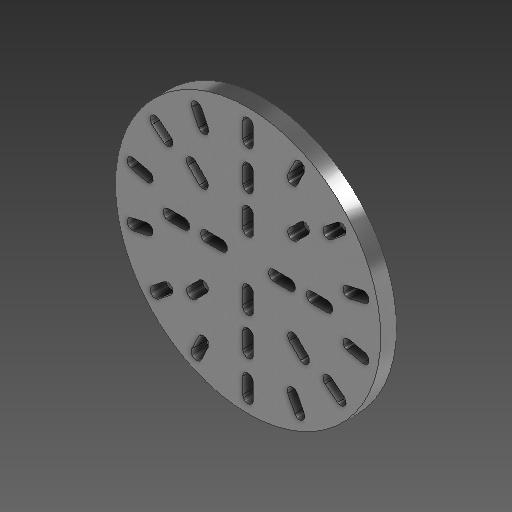
# Autodesk Inventor part: Circule pattern
Saved by Autodesk Inventor 2026.1 (Build 301233020, 233B)
## iProperties
Created: 2026-08-12
Part Number: Circule pattern
Material: Generic
Document SubType Name: Modeling
Designer: YmCris
Density: 1 g/cm^3
Appearance: Default
Author: YmCris
Autodesk Inventor part; units mm, degrees
ref_plane "YZ Plane" through (0, 0, 0) normal (1, 0, 0) x (0, 1, 0)
ref_plane "XZ Plane" through (0, 0, 0) normal (0, 1, 0) x (-1, 0, 0)
ref_plane "XY Plane" through (0, 0, 0) normal (0, 0, 1) x (1, 0, 0)
sketch "Sketch1" plane through (0, 0, 0) normal (0, 0, 1) x (1, 0, 0)
  circle A0 centre (0, 0) radius 1270
  line L0 (0, 0) -> (0, 1270)
  line L1 (0, 1270) -> (0, 635)
  line L2 (0, 1270) -> (0, 952.5)
  line L3 (50.8, 1136.3047) -> (50.8, 983.9047)
  line L4 (-50.8, 983.9047) -> (-50.8, 1136.3047)
  arc A1 (50.6913, 1136.3047) -> (-50.6913, 1136.3047) centre (0, 1136.3047) ccw
  line L5 (-50.8, 1136.3047) -> (-50.6913, 1136.3047)
  line L6 (50.6913, 1136.3047) -> (50.8, 1136.3047)
  arc A2 (-50.6913, 983.9047) -> (50.6913, 983.9047) centre (0, 983.9047) ccw
  line L7 (50.8, 983.9047) -> (50.6913, 983.9047)
  line L8 (-50.6913, 983.9047) -> (-50.8, 983.9047)
  line L9 (50.8, 609.0872) -> (50.8, 761.4872)
  line L10 (-50.8, 761.4872) -> (-50.8, 609.0872)
  arc A3 (50.6426, 761.4872) -> (-50.6426, 761.4872) centre (0, 761.4872) ccw
  line L11 (50.8, 761.4872) -> (50.6426, 761.4872)
  line L12 (-50.6426, 761.4872) -> (-50.8, 761.4872)
  arc A4 (-50.6426, 609.0872) -> (50.6426, 609.0872) centre (0, 609.0872) ccw
  line L13 (-50.8, 609.0872) -> (-50.6426, 609.0872)
  line L14 (50.6426, 609.0872) -> (50.8, 609.0872)
  line L15 (50.8, 401.6242) -> (50.8, 249.2242)
  line L16 (-50.8, 249.2242) -> (-50.8, 401.6242)
  arc A5 (50.8, 390.8967) -> (-50.8, 390.8967) centre (0, 401.6242) ccw
  line L17 (0, 325.4242) -> (22.9942, 325.4242)
  arc A6 (-50.8, 259.9518) -> (50.8, 259.9518) centre (0, 249.2242) ccw
  arc A7 (-472.5715, 864.4733) -> (-381.229, 908.4616) centre (-426.9002, 886.4675) ccw
  line L18 (-381.131, 908.5088) -> (-381.229, 908.4616)
  line L19 (-472.5715, 864.4733) -> (-472.6694, 864.4262)
  line L20 (-447.2549, 1045.8164) -> (-381.131, 908.5088)
  line L21 (-472.6694, 864.4262) -> (-538.7933, 1001.7338)
  line L22 (-447.3528, 1045.7692) -> (-447.2549, 1045.8164)
  arc A8 (-447.3528, 1045.7692) -> (-538.6954, 1001.781) centre (-493.0241, 1023.7751) ccw
  line L23 (-538.7933, 1001.7338) -> (-538.6954, 1001.781)
  arc A9 (-800.8531, 573.8225) -> (-737.6421, 653.0866) centre (-769.2476, 613.4545) ccw
  line L24 (-737.5744, 653.1716) -> (-737.6421, 653.0866)
  line L25 (-800.8531, 573.8225) -> (-800.9209, 573.7375)
  line L26 (-856.7255, 748.1914) -> (-737.5744, 653.1716)
  line L27 (-800.9209, 573.7375) -> (-920.072, 668.7573)
  line L28 (-856.7933, 748.1064) -> (-856.7255, 748.1914)
  arc A10 (-856.7933, 748.1064) -> (-920.0043, 668.8423) centre (-888.3988, 708.4744) ccw
  line L29 (-920.072, 668.7573) -> (-920.0043, 668.8423)
  arc A11 (-970.516, 169.519) -> (-947.9562, 268.3597) centre (-959.2361, 218.9394) ccw
  line L30 (-947.932, 268.4657) -> (-947.9562, 268.3597)
  line L31 (-970.516, 169.519) -> (-970.5402, 169.413)
  line L32 (-1096.5111, 302.3779) -> (-947.932, 268.4657)
  line L33 (-970.5402, 169.413) -> (-1119.1192, 203.3252)
  line L34 (-1096.5353, 302.2719) -> (-1096.5111, 302.3779)
  arc A12 (-1096.5353, 302.2719) -> (-1119.095, 203.4312) centre (-1107.8151, 252.8516) ccw
  line L35 (-1119.1192, 203.3252) -> (-1119.095, 203.4312)
  arc A13 (-947.9562, -268.3597) -> (-970.516, -169.519) centre (-959.2361, -218.9394) ccw
  line L36 (-970.5402, -169.413) -> (-970.516, -169.519)
  line L37 (-947.9562, -268.3597) -> (-947.932, -268.4657)
  line L38 (-1119.1192, -203.3252) -> (-970.5402, -169.413)
  line L39 (-947.932, -268.4657) -> (-1096.5111, -302.3779)
  line L40 (-1119.095, -203.4312) -> (-1119.1192, -203.3252)
  arc A14 (-1119.095, -203.4312) -> (-1096.5353, -302.2719) centre (-1107.8151, -252.8516) ccw
  line L41 (-1096.5111, -302.3779) -> (-1096.5353, -302.2719)
  arc A15 (-737.6421, -653.0866) -> (-800.8531, -573.8225) centre (-769.2476, -613.4545) ccw
  line L42 (-800.9209, -573.7375) -> (-800.8531, -573.8225)
  line L43 (-737.6421, -653.0866) -> (-737.5744, -653.1716)
  line L44 (-920.072, -668.7573) -> (-800.9209, -573.7375)
  line L45 (-737.5744, -653.1716) -> (-856.7255, -748.1914)
  line L46 (-920.0043, -668.8423) -> (-920.072, -668.7573)
  arc A16 (-920.0043, -668.8423) -> (-856.7933, -748.1064) centre (-888.3988, -708.4744) ccw
  line L47 (-856.7255, -748.1914) -> (-856.7933, -748.1064)
  arc A17 (-381.229, -908.4616) -> (-472.5715, -864.4733) centre (-426.9002, -886.4675) ccw
  line L48 (-472.6694, -864.4262) -> (-472.5715, -864.4733)
  line L49 (-381.229, -908.4616) -> (-381.131, -908.5088)
  line L50 (-538.7933, -1001.7338) -> (-472.6694, -864.4262)
  line L51 (-381.131, -908.5088) -> (-447.2549, -1045.8164)
  line L52 (-538.6954, -1001.781) -> (-538.7933, -1001.7338)
  arc A18 (-538.6954, -1001.781) -> (-447.3528, -1045.7692) centre (-493.0241, -1023.7751) ccw
  line L53 (-447.2549, -1045.8164) -> (-447.3528, -1045.7692)
  arc A19 (50.6913, -983.9047) -> (-50.6913, -983.9047) centre (0, -983.9047) ccw
  line L54 (-50.8, -983.9047) -> (-50.6913, -983.9047)
  line L55 (50.6913, -983.9047) -> (50.8, -983.9047)
  line L56 (-50.8, -1136.3047) -> (-50.8, -983.9047)
  line L57 (50.8, -983.9047) -> (50.8, -1136.3047)
  line L58 (-50.6913, -1136.3047) -> (-50.8, -1136.3047)
  arc A20 (-50.6913, -1136.3047) -> (50.6913, -1136.3047) centre (0, -1136.3047) ccw
  line L59 (50.8, -1136.3047) -> (50.6913, -1136.3047)
  arc A21 (472.5715, -864.4733) -> (381.229, -908.4616) centre (426.9002, -886.4675) ccw
  line L60 (381.131, -908.5088) -> (381.229, -908.4616)
  line L61 (472.5715, -864.4733) -> (472.6694, -864.4262)
  line L62 (447.2549, -1045.8164) -> (381.131, -908.5088)
  line L63 (472.6694, -864.4262) -> (538.7933, -1001.7338)
  line L64 (447.3528, -1045.7692) -> (447.2549, -1045.8164)
  arc A22 (447.3528, -1045.7692) -> (538.6954, -1001.781) centre (493.0241, -1023.7751) ccw
  line L65 (538.7933, -1001.7338) -> (538.6954, -1001.781)
  arc A23 (800.8531, -573.8225) -> (737.6421, -653.0866) centre (769.2476, -613.4545) ccw
  line L66 (737.5744, -653.1716) -> (737.6421, -653.0866)
  line L67 (800.8531, -573.8225) -> (800.9209, -573.7375)
  line L68 (856.7255, -748.1914) -> (737.5744, -653.1716)
  line L69 (800.9209, -573.7375) -> (920.072, -668.7573)
  line L70 (856.7933, -748.1064) -> (856.7255, -748.1914)
  arc A24 (856.7933, -748.1064) -> (920.0043, -668.8423) centre (888.3988, -708.4744) ccw
  line L71 (920.072, -668.7573) -> (920.0043, -668.8423)
  arc A25 (970.516, -169.519) -> (947.9562, -268.3597) centre (959.2361, -218.9394) ccw
  line L72 (947.932, -268.4657) -> (947.9562, -268.3597)
  line L73 (970.516, -169.519) -> (970.5402, -169.413)
  line L74 (1096.5111, -302.3779) -> (947.932, -268.4657)
  line L75 (970.5402, -169.413) -> (1119.1192, -203.3252)
  line L76 (1096.5353, -302.2719) -> (1096.5111, -302.3779)
  arc A26 (1096.5353, -302.2719) -> (1119.095, -203.4312) centre (1107.8151, -252.8516) ccw
  line L77 (1119.1192, -203.3252) -> (1119.095, -203.4312)
  arc A27 (947.9562, 268.3597) -> (970.516, 169.519) centre (959.2361, 218.9394) ccw
  line L78 (970.5402, 169.413) -> (970.516, 169.519)
  line L79 (947.9562, 268.3597) -> (947.932, 268.4657)
  line L80 (1119.1192, 203.3252) -> (970.5402, 169.413)
  line L81 (947.932, 268.4657) -> (1096.5111, 302.3779)
  line L82 (1119.095, 203.4312) -> (1119.1192, 203.3252)
  arc A28 (1119.095, 203.4312) -> (1096.5353, 302.2719) centre (1107.8151, 252.8516) ccw
  line L83 (1096.5111, 302.3779) -> (1096.5353, 302.2719)
  arc A29 (737.6421, 653.0866) -> (800.8531, 573.8225) centre (769.2476, 613.4545) ccw
  line L84 (800.9209, 573.7375) -> (800.8531, 573.8225)
  line L85 (737.6421, 653.0866) -> (737.5744, 653.1716)
  line L86 (920.072, 668.7573) -> (800.9209, 573.7375)
  line L87 (737.5744, 653.1716) -> (856.7255, 748.1914)
  line L88 (920.0043, 668.8423) -> (920.072, 668.7573)
  arc A30 (920.0043, 668.8423) -> (856.7933, 748.1064) centre (888.3988, 708.4744) ccw
  line L89 (856.7255, 748.1914) -> (856.7933, 748.1064)
  arc A31 (381.229, 908.4616) -> (472.5715, 864.4733) centre (426.9002, 886.4675) ccw
  line L90 (472.6694, 864.4262) -> (472.5715, 864.4733)
  line L91 (381.229, 908.4616) -> (381.131, 908.5088)
  line L92 (538.7933, 1001.7338) -> (472.6694, 864.4262)
  line L93 (381.131, 908.5088) -> (447.2549, 1045.8164)
  line L94 (538.6954, 1001.781) -> (538.7933, 1001.7338)
  arc A32 (538.6954, 1001.781) -> (447.3528, 1045.7692) centre (493.0241, 1023.7751) ccw
  line L95 (447.2549, 1045.8164) -> (447.3528, 1045.7692)
  line L96 (0, 0) -> (-898.0256, 898.0256)
  line L97 (-898.0256, 898.0256) -> (-449.0128, 449.0128)
  arc A33 (-502.643, 574.2625) -> (-574.2625, 502.643) centre (-538.4527, 538.4527) ccw
  line L98 (-502.5317, 574.3738) -> (-502.643, 574.2625)
  line L99 (-574.2625, 502.643) -> (-574.3738, 502.5317)
  line L100 (-394.7686, 466.6107) -> (-502.5317, 574.3738)
  line L101 (-574.3738, 502.5317) -> (-466.6107, 394.7686)
  line L102 (-394.8799, 466.4994) -> (-394.7686, 466.6107)
  arc A34 (-466.4994, 394.8799) -> (-394.8799, 466.4994) centre (-430.6897, 430.6897) ccw
  line L103 (-466.6107, 394.7686) -> (-466.4994, 394.8799)
  line L104 (0, 0) -> (-1270, 0)
  line L105 (-1270, 0) -> (-635, 0)
  arc A35 (-761.4872, 50.6426) -> (-761.4872, -50.6426) centre (-761.4872, 0) ccw
  line L106 (-761.4872, 50.8) -> (-761.4872, 50.6426)
  line L107 (-761.4872, -50.6426) -> (-761.4872, -50.8)
  line L108 (-609.0872, 50.8) -> (-761.4872, 50.8)
  line L109 (-761.4872, -50.8) -> (-609.0872, -50.8)
  line L110 (-609.0872, 50.6426) -> (-609.0872, 50.8)
  arc A36 (-609.0872, -50.6426) -> (-609.0872, 50.6426) centre (-609.0872, 0) ccw
  line L111 (-609.0872, -50.8) -> (-609.0872, -50.6426)
  line L112 (0, 0) -> (-898.0256, -898.0256)
  line L113 (-898.0256, -898.0256) -> (-449.0128, -449.0128)
  arc A37 (-574.2625, -502.643) -> (-502.643, -574.2625) centre (-538.4527, -538.4527) ccw
  line L114 (-574.3738, -502.5317) -> (-574.2625, -502.643)
  line L115 (-502.643, -574.2625) -> (-502.5317, -574.3738)
  line L116 (-466.6107, -394.7686) -> (-574.3738, -502.5317)
  line L117 (-502.5317, -574.3738) -> (-394.7686, -466.6107)
  line L118 (-466.4994, -394.8799) -> (-466.6107, -394.7686)
  arc A38 (-394.8799, -466.4994) -> (-466.4994, -394.8799) centre (-430.6897, -430.6897) ccw
  line L119 (-394.7686, -466.6107) -> (-394.8799, -466.4994)
  line L120 (0, 0) -> (0, -1270)
  line L121 (0, -1270) -> (0, -635)
  arc A39 (-50.6426, -761.4872) -> (50.6426, -761.4872) centre (0, -761.4872) ccw
  line L122 (-50.8, -761.4872) -> (-50.6426, -761.4872)
  line L123 (50.6426, -761.4872) -> (50.8, -761.4872)
  line L124 (-50.8, -609.0872) -> (-50.8, -761.4872)
  line L125 (50.8, -761.4872) -> (50.8, -609.0872)
  line L126 (-50.6426, -609.0872) -> (-50.8, -609.0872)
  arc A40 (50.6426, -609.0872) -> (-50.6426, -609.0872) centre (0, -609.0872) ccw
  line L127 (50.8, -609.0872) -> (50.6426, -609.0872)
  line L128 (0, 0) -> (898.0256, -898.0256)
  line L129 (898.0256, -898.0256) -> (449.0128, -449.0128)
  arc A41 (502.643, -574.2625) -> (574.2625, -502.643) centre (538.4527, -538.4527) ccw
  line L130 (502.5317, -574.3738) -> (502.643, -574.2625)
  line L131 (574.2625, -502.643) -> (574.3738, -502.5317)
  line L132 (394.7686, -466.6107) -> (502.5317, -574.3738)
  line L133 (574.3738, -502.5317) -> (466.6107, -394.7686)
  line L134 (394.8799, -466.4994) -> (394.7686, -466.6107)
  arc A42 (466.4994, -394.8799) -> (394.8799, -466.4994) centre (430.6897, -430.6897) ccw
  line L135 (466.6107, -394.7686) -> (466.4994, -394.8799)
  line L136 (0, 0) -> (1270, 0)
  line L137 (1270, 0) -> (635, 0)
  arc A43 (761.4872, -50.6426) -> (761.4872, 50.6426) centre (761.4872, 0) ccw
  line L138 (761.4872, -50.8) -> (761.4872, -50.6426)
  line L139 (761.4872, 50.6426) -> (761.4872, 50.8)
  line L140 (609.0872, -50.8) -> (761.4872, -50.8)
  line L141 (761.4872, 50.8) -> (609.0872, 50.8)
  line L142 (609.0872, -50.6426) -> (609.0872, -50.8)
  arc A44 (609.0872, 50.6426) -> (609.0872, -50.6426) centre (609.0872, 0) ccw
  line L143 (609.0872, 50.8) -> (609.0872, 50.6426)
  line L144 (0, 0) -> (898.0256, 898.0256)
  line L145 (898.0256, 898.0256) -> (449.0128, 449.0128)
  arc A45 (574.2625, 502.643) -> (502.643, 574.2625) centre (538.4527, 538.4527) ccw
  line L146 (574.3738, 502.5317) -> (574.2625, 502.643)
  line L147 (502.643, 574.2625) -> (502.5317, 574.3738)
  line L148 (466.6107, 394.7686) -> (574.3738, 502.5317)
  line L149 (502.5317, 574.3738) -> (394.7686, 466.6107)
  line L150 (466.4994, 394.8799) -> (466.6107, 394.7686)
  arc A46 (394.8799, 466.4994) -> (466.4994, 394.8799) centre (430.6897, 430.6897) ccw
  line L151 (394.7686, 466.6107) -> (394.8799, 466.4994)
  arc A47 (-390.8967, 50.8) -> (-390.8967, -50.8) centre (-401.6242, 0) ccw
  line L152 (-249.2242, -50.8) -> (-401.6242, -50.8)
  line L153 (-325.4242, 0) -> (-325.4242, 22.9942)
  line L154 (-401.6242, 50.8) -> (-249.2242, 50.8)
  arc A48 (-259.9518, -50.8) -> (-259.9518, 50.8) centre (-249.2242, 0) ccw
  line L155 (0, 0) -> (-1270, 0)
  arc A49 (-50.8, -390.8967) -> (50.8, -390.8967) centre (0, -401.6242) ccw
  line L156 (50.8, -249.2242) -> (50.8, -401.6242)
  line L157 (0, -325.4242) -> (-22.9942, -325.4242)
  line L158 (-50.8, -401.6242) -> (-50.8, -249.2242)
  arc A50 (50.8, -259.9518) -> (-50.8, -259.9518) centre (0, -249.2242) ccw
  line L159 (0, 0) -> (0, -1270)
  arc A51 (390.8967, -50.8) -> (390.8967, 50.8) centre (401.6242, 0) ccw
  line L160 (249.2242, 50.8) -> (401.6242, 50.8)
  line L161 (325.4242, 0) -> (325.4242, -22.9942)
  line L162 (401.6242, -50.8) -> (249.2242, -50.8)
  arc A52 (259.9518, 50.8) -> (259.9518, -50.8) centre (249.2242, 0) ccw
  line L163 (0, 0) -> (1270, 0)
  point P0 (-413.2743, 858.1728)
  point P1 (-744.6945, 593.874)
  point P2 (-928.6188, 211.9512)
  point P3 (-928.6188, -211.9512)
  point P4 (-744.6945, -593.874)
  point P5 (-413.2743, -858.1728)
  point P6 (0, -952.5)
  point P7 (413.2743, -858.1728)
  point P8 (744.6945, -593.874)
  point P9 (928.6188, -211.9512)
  point P10 (928.6188, 211.9512)
  point P11 (744.6945, 593.874)
  point P12 (413.2743, 858.1728)
  point P13 (-230.1097, 230.1097)
  point P14 (-283.9912, 283.9912)
  point P15 (-673.5192, 673.5192)
  point P16 (-952.5, 0)
  point P17 (-230.1097, -230.1097)
  point P18 (-283.9912, -283.9912)
  point P19 (-673.5192, -673.5192)
  point P20 (0, -952.5)
  point P21 (230.1097, -230.1097)
  point P22 (283.9912, -283.9912)
  point P23 (673.5192, -673.5192)
  point P24 (952.5, 0)
  point P25 (230.1097, 230.1097)
  point P26 (283.9912, 283.9912)
  point P27 (673.5192, 673.5192)
  point P28 (259.9518, 50.8)
  point P29 (259.9518, -50.8)
  point P30 (-50.8, -259.9518)
  point P31 (-259.9518, -50.8)
  point P32 (-259.9518, 50.8)
  point P33 (50.8, 259.9518)
  point P34 (-50.8, 259.9518)
  dimension "d0" = 2540
  dimension "d9" = 360
  dimension "d13" = 360
  dimension "d17" = 360
  constraints: 328 end point, 104 point on circle, 52 centre point, 30 point on line, 11 parallel, 5 horizontal, 4 perpendicular, 3 symmetric about line, 2 midpoint, 1 coincident, 1 vertical alignment, 564 other
sketch "Sketch2" plane through (0, 0, 0) normal (0, 0, 1) x (1, 0, 0)
  point P0 (0, 0)
extrude "Extrusion1" add sketch "Sketch1" along normal mid plane 152.4 contours L136 A43 L139 L141 L143 A44 A51 L160 A52 L144 A46 L150 L148 L146 A45 A0 | A0 L128 A41 L131 L133 L135 A42 L136 A52 L162 A51 A44 L142 L140 L138 A43 | L144 A45 L147 L149 L151 A46 L0 A6 L15 A5 A4 L14 L9 L11 A3 A2 L7 L3 L6 A1 A0 | A0 L120 A20 L59 L57 L55 A19 A39 L123 L125 L127 A40 A49 L156 A50 L128 A42 L134 L132 L130 A41 | L0 A1 L5 L4 L8 A2 A3 L12 L10 L13 A4 A5 L16 A6 L96 A34 L102 L100 L98 A33 A0 | A0 L112 A37 L115 L117 L119 A38 L120 A50 L158 A49 A40 L126 L124 L122 A39 A19 L54 L56 L58 A20 | L96 A33 L99 L101 L103 A34 L104 A48 L154 A47 A36 L110 L108 L106 A35 A0 | A0 L104 A35 L107 L109 L111 A36 A47 L152 A48 L112 A38 L118 L116 L114 A37
body "Solid1"
